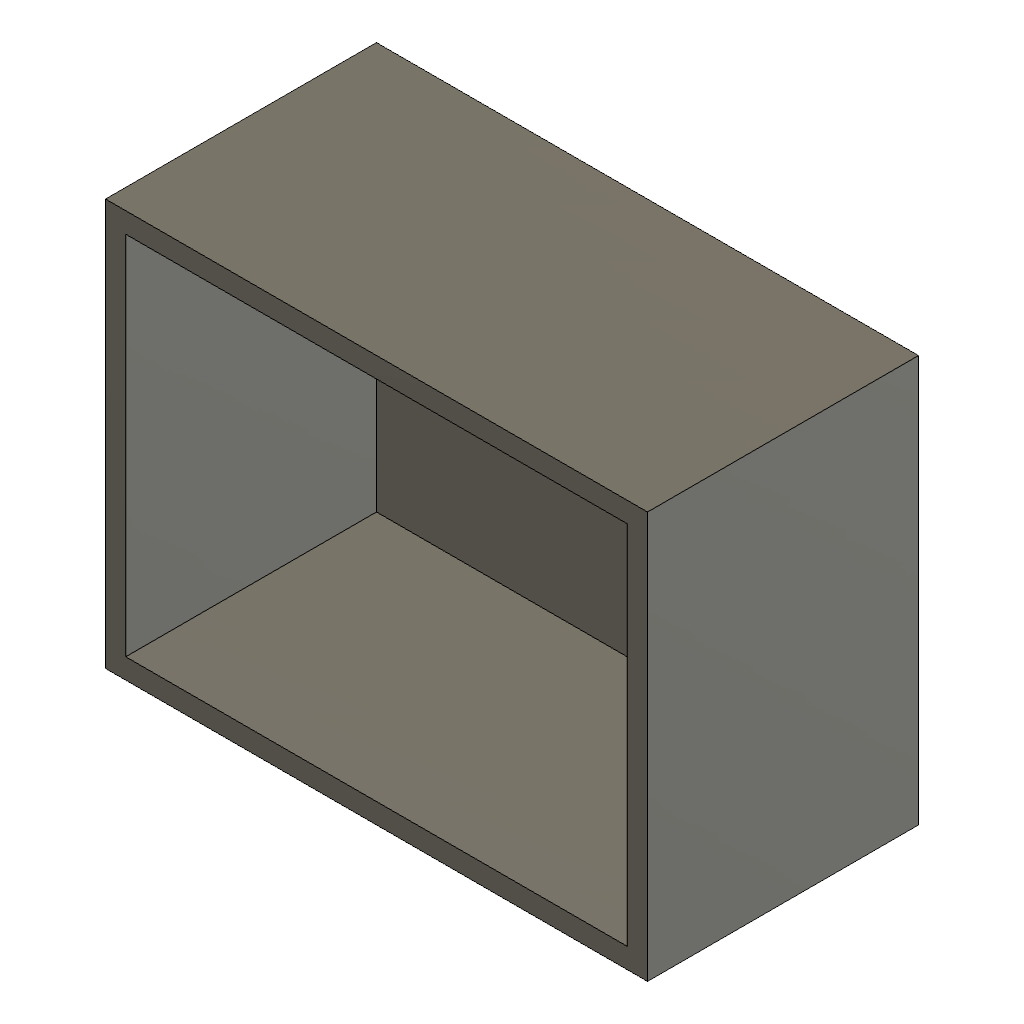
shell_rounded (Autodesk Fusion 360 design; units mm, degrees)
part number: 2026-10-20-19-17-55-827
Autodesk Fusion 360 part; units mm, degrees
sketch "Sketch1" plane through (0, 0, 0) normal (0, 0, 1) x (1, 0, 0)
  line L0 (10, 10) -> (50, 10)
  line L1 (50, 10) -> (50, 40)
  line L2 (50, 40) -> (10, 40)
  line L3 (10, 40) -> (10, 10)
extrude "SeedExtrusion" add sketch "Sketch1" along normal blind 20
shell "ProbeBodyTool" thickness 1.5 removed faces 1 at (23.3333, 30, 20)
